Autodesk Fusion 360 part; units mm, degrees
(part 4 of 5)
sketch "草图4 (3)" plane through (0, 0, 4.8) normal (0, 0, 1) x (1, 0, 0) in component "03_可换镜像凹纹压片"
  line L0 (-27.9663, -1.3739) -> (-27.8652, -2.7445)
  line L1 (-27.8652, -2.7445) -> (-27.6969, -4.1085)
  line L2 (-27.6969, -4.1085) -> (-27.462, -5.4625)
  line L3 (-27.462, -5.4625) -> (-27.1609, -6.8034)
  line L4 (-27.1609, -6.8034) -> (-26.7943, -8.128)
  line L5 (-26.7943, -8.128) -> (-26.3632, -9.4329)
  line L6 (-26.3632, -9.4329) -> (-25.8686, -10.7151)
  line L7 (-25.8686, -10.7151) -> (-25.3117, -11.9715)
  line L8 (-25.3117, -11.9715) -> (-24.6938, -13.1991)
  line L9 (-24.6938, -13.1991) -> (-24.0164, -14.3949)
  line L10 (-24.0164, -14.3949) -> (-23.2811, -15.556)
  line L11 (-23.2811, -15.556) -> (-22.4898, -16.6796)
  line L12 (-22.4898, -16.6796) -> (-21.6443, -17.763)
  line L13 (-21.6443, -17.763) -> (-20.7466, -18.8037)
  line L14 (-20.7466, -18.8037) -> (-19.799, -19.799)
  line L15 (-19.799, -19.799) -> (-18.8037, -20.7466)
  line L16 (-18.8037, -20.7466) -> (-17.763, -21.6443)
  line L17 (-17.763, -21.6443) -> (-16.6796, -22.4898)
  line L18 (-16.6796, -22.4898) -> (-15.556, -23.2811)
  line L19 (-15.556, -23.2811) -> (-14.3949, -24.0164)
  line L20 (-14.3949, -24.0164) -> (-13.1991, -24.6938)
  line L21 (-13.1991, -24.6938) -> (-11.9715, -25.3117)
  line L22 (-11.9715, -25.3117) -> (-10.7151, -25.8686)
  line L23 (-10.7151, -25.8686) -> (-9.4329, -26.3632)
  line L24 (-9.4329, -26.3632) -> (-8.128, -26.7943)
  line L25 (-8.128, -26.7943) -> (-6.8034, -27.1609)
  line L26 (-6.8034, -27.1609) -> (-5.4625, -27.462)
  line L27 (-5.4625, -27.462) -> (-4.1085, -27.6969)
  line L28 (-4.1085, -27.6969) -> (-2.7445, -27.8652)
  line L29 (-2.7445, -27.8652) -> (-1.3739, -27.9663)
  line L30 (-1.3739, -27.9663) -> (0, -28)
  line L31 (0, -28) -> (1.3739, -27.9663)
  line L32 (1.3739, -27.9663) -> (2.7445, -27.8652)
  line L33 (2.7445, -27.8652) -> (4.1085, -27.6969)
  line L34 (4.1085, -27.6969) -> (5.4625, -27.462)
  line L35 (5.4625, -27.462) -> (6.8034, -27.1609)
  line L36 (6.8034, -27.1609) -> (8.128, -26.7943)
  line L37 (8.128, -26.7943) -> (9.4329, -26.3632)
  line L38 (9.4329, -26.3632) -> (10.7151, -25.8686)
  line L39 (10.7151, -25.8686) -> (11.9715, -25.3117)
  line L40 (11.9715, -25.3117) -> (13.1991, -24.6938)
  line L41 (13.1991, -24.6938) -> (14.3949, -24.0164)
  line L42 (14.3949, -24.0164) -> (15.556, -23.2811)
  line L43 (15.556, -23.2811) -> (16.6796, -22.4898)
  line L44 (16.6796, -22.4898) -> (17.763, -21.6443)
  line L45 (17.763, -21.6443) -> (18.8037, -20.7466)
  line L46 (18.8037, -20.7466) -> (19.799, -19.799)
  line L47 (19.799, -19.799) -> (20.7466, -18.8037)
  line L48 (20.7466, -18.8037) -> (21.6443, -17.763)
  line L49 (21.6443, -17.763) -> (22.4898, -16.6796)
  line L50 (22.4898, -16.6796) -> (23.2811, -15.556)
  line L51 (23.2811, -15.556) -> (24.0164, -14.3949)
  line L52 (24.0164, -14.3949) -> (24.6938, -13.1991)
  line L53 (24.6938, -13.1991) -> (25.3117, -11.9715)
  line L54 (25.3117, -11.9715) -> (25.8686, -10.7151)
  line L55 (25.8686, -10.7151) -> (26.3632, -9.4329)
  line L56 (26.3632, -9.4329) -> (26.7943, -8.128)
  line L57 (26.7943, -8.128) -> (27.1609, -6.8034)
  line L58 (27.1609, -6.8034) -> (27.462, -5.4625)
  line L59 (27.462, -5.4625) -> (27.6969, -4.1085)
  line L60 (27.6969, -4.1085) -> (27.8652, -2.7445)
  line L61 (27.8652, -2.7445) -> (27.9663, -1.3739)
  line L62 (27.9663, -1.3739) -> (28, 0)
  line L63 (28, 0) -> (27.9663, 1.3739)
  line L64 (27.9663, 1.3739) -> (27.8652, 2.7445)
  line L65 (27.8652, 2.7445) -> (27.6969, 4.1085)
  line L66 (27.6969, 4.1085) -> (27.462, 5.4625)
  line L67 (27.462, 5.4625) -> (27.1609, 6.8034)
  line L68 (27.1609, 6.8034) -> (26.7943, 8.128)
  line L69 (26.7943, 8.128) -> (26.3632, 9.4329)
  line L70 (26.3632, 9.4329) -> (25.8686, 10.7151)
  line L71 (25.8686, 10.7151) -> (25.3117, 11.9715)
  line L72 (25.3117, 11.9715) -> (24.6938, 13.1991)
  line L73 (24.6938, 13.1991) -> (24.0164, 14.3949)
  line L74 (24.0164, 14.3949) -> (23.2811, 15.556)
  line L75 (23.2811, 15.556) -> (22.4898, 16.6796)
  line L76 (22.4898, 16.6796) -> (21.6443, 17.763)
  line L77 (21.6443, 17.763) -> (20.7466, 18.8037)
  line L78 (20.7466, 18.8037) -> (19.799, 19.799)
  line L79 (19.799, 19.799) -> (18.8037, 20.7466)
  line L80 (18.8037, 20.7466) -> (17.763, 21.6443)
  line L81 (17.763, 21.6443) -> (16.6796, 22.4898)
  line L82 (16.6796, 22.4898) -> (15.556, 23.2811)
  line L83 (15.556, 23.2811) -> (14.3949, 24.0164)
  line L84 (14.3949, 24.0164) -> (13.1991, 24.6938)
  line L85 (13.1991, 24.6938) -> (11.9715, 25.3117)
  line L86 (11.9715, 25.3117) -> (10.7151, 25.8686)
  line L87 (10.7151, 25.8686) -> (9.4329, 26.3632)
  line L88 (9.4329, 26.3632) -> (8.128, 26.7943)
  line L89 (8.128, 26.7943) -> (6.8034, 27.1609)
  line L90 (6.8034, 27.1609) -> (5.4625, 27.462)
  line L91 (5.4625, 27.462) -> (4.1085, 27.6969)
  line L92 (4.1085, 27.6969) -> (2.7445, 27.8652)
  line L93 (2.7445, 27.8652) -> (1.3739, 27.9663)
  line L94 (1.3739, 27.9663) -> (0, 28)
  line L95 (0, 28) -> (-1.3739, 27.9663)
  line L96 (-1.3739, 27.9663) -> (-2.7445, 27.8652)
  line L97 (-2.7445, 27.8652) -> (-4.1085, 27.6969)
  line L98 (-4.1085, 27.6969) -> (-5.4625, 27.462)
  line L99 (-5.4625, 27.462) -> (-6.8034, 27.1609)
  line L100 (-6.8034, 27.1609) -> (-8.128, 26.7943)
  line L101 (-8.128, 26.7943) -> (-9.4329, 26.3632)
  line L102 (-9.4329, 26.3632) -> (-10.7151, 25.8686)
  line L103 (-10.7151, 25.8686) -> (-11.9715, 25.3117)
  line L104 (-11.9715, 25.3117) -> (-13.1991, 24.6938)
  line L105 (-13.1991, 24.6938) -> (-14.3949, 24.0164)
  line L106 (-14.3949, 24.0164) -> (-15.556, 23.2811)
  line L107 (-15.556, 23.2811) -> (-16.6796, 22.4898)
  line L108 (-16.6796, 22.4898) -> (-17.763, 21.6443)
  line L109 (-17.763, 21.6443) -> (-18.8037, 20.7466)
  line L110 (-18.8037, 20.7466) -> (-19.799, 19.799)
  line L111 (-19.799, 19.799) -> (-20.7466, 18.8037)
  line L112 (-20.7466, 18.8037) -> (-21.6443, 17.763)
  line L113 (-21.6443, 17.763) -> (-22.4898, 16.6796)
  line L114 (-22.4898, 16.6796) -> (-23.2811, 15.556)
  line L115 (-23.2811, 15.556) -> (-24.0164, 14.3949)
  line L116 (-24.0164, 14.3949) -> (-24.6938, 13.1991)
  line L117 (-24.6938, 13.1991) -> (-25.3117, 11.9715)
  line L118 (-25.3117, 11.9715) -> (-25.8686, 10.7151)
  line L119 (-25.8686, 10.7151) -> (-26.3632, 9.4329)
  line L120 (-26.3632, 9.4329) -> (-26.7943, 8.128)
  line L121 (-26.7943, 8.128) -> (-27.1609, 6.8034)
  line L122 (-27.1609, 6.8034) -> (-27.462, 5.4625)
  line L123 (-27.462, 5.4625) -> (-27.6969, 4.1085)
  line L124 (-27.6969, 4.1085) -> (-27.8652, 2.7445)
  line L125 (-27.8652, 2.7445) -> (-27.9663, 1.3739)
  line L126 (-27.9663, 1.3739) -> (-28, 0)
  line L127 (-28, 0) -> (-27.9663, -1.3739)
  line L128 (-27.1, 0) -> (-27.0674, 1.3297)
  line L129 (-27.0674, 1.3297) -> (-26.9695, 2.6563)
  line L130 (-26.9695, 2.6563) -> (-26.8067, 3.9764)
  line L131 (-26.8067, 3.9764) -> (-26.5793, 5.2869)
  line L132 (-26.5793, 5.2869) -> (-26.2878, 6.5848)
  line L133 (-26.2878, 6.5848) -> (-25.9331, 7.8667)
  line L134 (-25.9331, 7.8667) -> (-25.5158, 9.1297)
  line L135 (-25.5158, 9.1297) -> (-25.0371, 10.3707)
  line L136 (-25.0371, 10.3707) -> (-24.4981, 11.5867)
  line L137 (-24.4981, 11.5867) -> (-23.9001, 12.7749)
  line L138 (-23.9001, 12.7749) -> (-23.2444, 13.9322)
  line L139 (-23.2444, 13.9322) -> (-22.5328, 15.056)
  line L140 (-22.5328, 15.056) -> (-21.7669, 16.1435)
  line L141 (-21.7669, 16.1435) -> (-20.9486, 17.1921)
  line L142 (-20.9486, 17.1921) -> (-20.0798, 18.1992)
  line L143 (-20.0798, 18.1992) -> (-19.1626, 19.1626)
  line L144 (-19.1626, 19.1626) -> (-18.1992, 20.0798)
  line L145 (-18.1992, 20.0798) -> (-17.1921, 20.9486)
  line L146 (-17.1921, 20.9486) -> (-16.1435, 21.7669)
  line L147 (-16.1435, 21.7669) -> (-15.056, 22.5328)
  line L148 (-15.056, 22.5328) -> (-13.9322, 23.2444)
  line L149 (-13.9322, 23.2444) -> (-12.7749, 23.9001)
  line L150 (-12.7749, 23.9001) -> (-11.5867, 24.4981)
  line L151 (-11.5867, 24.4981) -> (-10.3707, 25.0371)
  line L152 (-10.3707, 25.0371) -> (-9.1297, 25.5158)
  line L153 (-9.1297, 25.5158) -> (-7.8667, 25.9331)
  line L154 (-7.8667, 25.9331) -> (-6.5848, 26.2878)
  line L155 (-6.5848, 26.2878) -> (-5.2869, 26.5793)
  line L156 (-5.2869, 26.5793) -> (-3.9764, 26.8067)
  line L157 (-3.9764, 26.8067) -> (-2.6563, 26.9695)
  line L158 (-2.6563, 26.9695) -> (-1.3297, 27.0674)
  line L159 (-1.3297, 27.0674) -> (0, 27.1)
  line L160 (0, 27.1) -> (1.3297, 27.0674)
  line L161 (1.3297, 27.0674) -> (2.6563, 26.9695)
  line L162 (2.6563, 26.9695) -> (3.9764, 26.8067)
  line L163 (3.9764, 26.8067) -> (5.2869, 26.5793)
  line L164 (5.2869, 26.5793) -> (6.5848, 26.2878)
  line L165 (6.5848, 26.2878) -> (7.8667, 25.9331)
  line L166 (7.8667, 25.9331) -> (9.1297, 25.5158)
  line L167 (9.1297, 25.5158) -> (10.3707, 25.0371)
  line L168 (10.3707, 25.0371) -> (11.5867, 24.4981)
  line L169 (11.5867, 24.4981) -> (12.7749, 23.9001)
  line L170 (12.7749, 23.9001) -> (13.9322, 23.2444)
  line L171 (13.9322, 23.2444) -> (15.056, 22.5328)
  line L172 (15.056, 22.5328) -> (16.1435, 21.7669)
  line L173 (16.1435, 21.7669) -> (17.1921, 20.9486)
  line L174 (17.1921, 20.9486) -> (18.1992, 20.0798)
  line L175 (18.1992, 20.0798) -> (19.1626, 19.1626)
  line L176 (19.1626, 19.1626) -> (20.0798, 18.1992)
  line L177 (20.0798, 18.1992) -> (20.9486, 17.1921)
  line L178 (20.9486, 17.1921) -> (21.7669, 16.1435)
  line L179 (21.7669, 16.1435) -> (22.5328, 15.056)
  line L180 (22.5328, 15.056) -> (23.2444, 13.9322)
  line L181 (23.2444, 13.9322) -> (23.9001, 12.7749)
  line L182 (23.9001, 12.7749) -> (24.4981, 11.5867)
  line L183 (24.4981, 11.5867) -> (25.0371, 10.3707)
  line L184 (25.0371, 10.3707) -> (25.5158, 9.1297)
  line L185 (25.5158, 9.1297) -> (25.9331, 7.8667)
  line L186 (25.9331, 7.8667) -> (26.2878, 6.5848)
  line L187 (26.2878, 6.5848) -> (26.5793, 5.2869)
  line L188 (26.5793, 5.2869) -> (26.8067, 3.9764)
  line L189 (26.8067, 3.9764) -> (26.9695, 2.6563)
  line L190 (26.9695, 2.6563) -> (27.0674, 1.3297)
  line L191 (27.0674, 1.3297) -> (27.1, 0)
  line L192 (27.1, 0) -> (27.0674, -1.3297)
  line L193 (27.0674, -1.3297) -> (26.9695, -2.6563)
  line L194 (26.9695, -2.6563) -> (26.8067, -3.9764)
  line L195 (26.8067, -3.9764) -> (26.5793, -5.2869)
  line L196 (26.5793, -5.2869) -> (26.2878, -6.5848)
  line L197 (26.2878, -6.5848) -> (25.9331, -7.8667)
  line L198 (25.9331, -7.8667) -> (25.5158, -9.1297)
  line L199 (25.5158, -9.1297) -> (25.0371, -10.3707)
  line L200 (25.0371, -10.3707) -> (24.4981, -11.5867)
  line L201 (24.4981, -11.5867) -> (23.9001, -12.7749)
  line L202 (23.9001, -12.7749) -> (23.2444, -13.9322)
  line L203 (23.2444, -13.9322) -> (22.5328, -15.056)
  line L204 (22.5328, -15.056) -> (21.7669, -16.1435)
  line L205 (21.7669, -16.1435) -> (20.9486, -17.1921)
  line L206 (20.9486, -17.1921) -> (20.0798, -18.1992)
  line L207 (20.0798, -18.1992) -> (19.1626, -19.1626)
  line L208 (19.1626, -19.1626) -> (18.1992, -20.0798)
  line L209 (18.1992, -20.0798) -> (17.1921, -20.9486)
  line L210 (17.1921, -20.9486) -> (16.1435, -21.7669)
  line L211 (16.1435, -21.7669) -> (15.056, -22.5328)
  line L212 (15.056, -22.5328) -> (13.9322, -23.2444)
  line L213 (13.9322, -23.2444) -> (12.7749, -23.9001)
  line L214 (12.7749, -23.9001) -> (11.5867, -24.4981)
  line L215 (11.5867, -24.4981) -> (10.3707, -25.0371)
  line L216 (10.3707, -25.0371) -> (9.1297, -25.5158)
  line L217 (9.1297, -25.5158) -> (7.8667, -25.9331)
  line L218 (7.8667, -25.9331) -> (6.5848, -26.2878)
  line L219 (6.5848, -26.2878) -> (5.2869, -26.5793)
  line L220 (5.2869, -26.5793) -> (3.9764, -26.8067)
  line L221 (3.9764, -26.8067) -> (2.6563, -26.9695)
  line L222 (2.6563, -26.9695) -> (1.3297, -27.0674)
  line L223 (1.3297, -27.0674) -> (0, -27.1)
  line L224 (0, -27.1) -> (-1.3297, -27.0674)
  line L225 (-1.3297, -27.0674) -> (-2.6563, -26.9695)
  line L226 (-2.6563, -26.9695) -> (-3.9764, -26.8067)
  line L227 (-3.9764, -26.8067) -> (-5.2869, -26.5793)
  line L228 (-5.2869, -26.5793) -> (-6.5848, -26.2878)
  line L229 (-6.5848, -26.2878) -> (-7.8667, -25.9331)
  line L230 (-7.8667, -25.9331) -> (-9.1297, -25.5158)
  line L231 (-9.1297, -25.5158) -> (-10.3707, -25.0371)
  line L232 (-10.3707, -25.0371) -> (-11.5867, -24.4981)
  line L233 (-11.5867, -24.4981) -> (-12.7749, -23.9001)
  line L234 (-12.7749, -23.9001) -> (-13.9322, -23.2444)
  line L235 (-13.9322, -23.2444) -> (-15.056, -22.5328)
  line L236 (-15.056, -22.5328) -> (-16.1435, -21.7669)
  line L237 (-16.1435, -21.7669) -> (-17.1921, -20.9486)
  line L238 (-17.1921, -20.9486) -> (-18.1992, -20.0798)
  line L239 (-18.1992, -20.0798) -> (-19.1626, -19.1626)
  line L240 (-19.1626, -19.1626) -> (-20.0798, -18.1992)
  line L241 (-20.0798, -18.1992) -> (-20.9486, -17.1921)
  line L242 (-20.9486, -17.1921) -> (-21.7669, -16.1435)
  line L243 (-21.7669, -16.1435) -> (-22.5328, -15.056)
  line L244 (-22.5328, -15.056) -> (-23.2444, -13.9322)
  line L245 (-23.2444, -13.9322) -> (-23.9001, -12.7749)
  line L246 (-23.9001, -12.7749) -> (-24.4981, -11.5867)
  line L247 (-24.4981, -11.5867) -> (-25.0371, -10.3707)
  line L248 (-25.0371, -10.3707) -> (-25.5158, -9.1297)
  line L249 (-25.5158, -9.1297) -> (-25.9331, -7.8667)
  line L250 (-25.9331, -7.8667) -> (-26.2878, -6.5848)
  line L251 (-26.2878, -6.5848) -> (-26.5793, -5.2869)
  line L252 (-26.5793, -5.2869) -> (-26.8067, -3.9764)
  line L253 (-26.8067, -3.9764) -> (-26.9695, -2.6563)
  line L254 (-26.9695, -2.6563) -> (-27.0674, -1.3297)
  line L255 (-27.0674, -1.3297) -> (-27.1, 0)
extrude "镜像凹纹_001 (1)" cut sketch "草图4 (3)" along normal blind 1.23 bodies 3 in component "03_可换镜像凹纹压片"
ref_plane "工作平面4" through (0, 0, 4.8) normal (0, 0, 1) x (1, 0, 0) in component "03_可换镜像凹纹压片"
sketch "草图5 (3)" plane through (0, 0, 4.8) normal (0, 0, 1) x (1, 0, 0) in component "03_可换镜像凹纹压片"
  line L0 (-18.4577, -0.9068) -> (-18.391, -1.8114)
  line L1 (-18.391, -1.8114) -> (-18.28, -2.7116)
  line L2 (-18.28, -2.7116) -> (-18.1249, -3.6053)
  line L3 (-18.1249, -3.6053) -> (-17.9262, -4.4903)
  line L4 (-17.9262, -4.4903) -> (-17.6843, -5.3645)
  line L5 (-17.6843, -5.3645) -> (-17.3997, -6.2257)
  line L6 (-17.3997, -6.2257) -> (-17.0733, -7.072)
  line L7 (-17.0733, -7.072) -> (-16.7057, -7.9012)
  line L8 (-16.7057, -7.9012) -> (-16.2979, -8.7114)
  line L9 (-16.2979, -8.7114) -> (-15.8508, -9.5006)
  line L10 (-15.8508, -9.5006) -> (-15.3656, -10.2669)
  line L11 (-15.3656, -10.2669) -> (-14.8433, -11.0085)
  line L12 (-14.8433, -11.0085) -> (-14.2852, -11.7236)
  line L13 (-14.2852, -11.7236) -> (-13.6928, -12.4104)
  line L14 (-13.6928, -12.4104) -> (-13.0673, -13.0673)
  line L15 (-13.0673, -13.0673) -> (-12.4104, -13.6928)
  line L16 (-12.4104, -13.6928) -> (-11.7236, -14.2852)
  line L17 (-11.7236, -14.2852) -> (-11.0085, -14.8433)
  line L18 (-11.0085, -14.8433) -> (-10.2669, -15.3656)
  line L19 (-10.2669, -15.3656) -> (-9.5006, -15.8508)
  line L20 (-9.5006, -15.8508) -> (-8.7114, -16.2979)
  line L21 (-8.7114, -16.2979) -> (-7.9012, -16.7057)
  line L22 (-7.9012, -16.7057) -> (-7.072, -17.0733)
  line L23 (-7.072, -17.0733) -> (-6.2257, -17.3997)
  line L24 (-6.2257, -17.3997) -> (-5.3645, -17.6843)
  line L25 (-5.3645, -17.6843) -> (-4.4903, -17.9262)
  line L26 (-4.4903, -17.9262) -> (-3.6053, -18.1249)
  line L27 (-3.6053, -18.1249) -> (-2.7116, -18.28)
  line L28 (-2.7116, -18.28) -> (-1.8114, -18.391)
  line L29 (-1.8114, -18.391) -> (-0.9068, -18.4577)
  line L30 (-0.9068, -18.4577) -> (0, -18.48)
  line L31 (0, -18.48) -> (0.9068, -18.4577)
  line L32 (0.9068, -18.4577) -> (1.8114, -18.391)
  line L33 (1.8114, -18.391) -> (2.7116, -18.28)
  line L34 (2.7116, -18.28) -> (3.6053, -18.1249)
  line L35 (3.6053, -18.1249) -> (4.4903, -17.9262)
  line L36 (4.4903, -17.9262) -> (5.3645, -17.6843)
  line L37 (5.3645, -17.6843) -> (6.2257, -17.3997)
  line L38 (6.2257, -17.3997) -> (7.072, -17.0733)
  line L39 (7.072, -17.0733) -> (7.9012, -16.7057)
  line L40 (7.9012, -16.7057) -> (8.7114, -16.2979)
  line L41 (8.7114, -16.2979) -> (9.5006, -15.8508)
  line L42 (9.5006, -15.8508) -> (10.2669, -15.3656)
  line L43 (10.2669, -15.3656) -> (11.0085, -14.8433)
  line L44 (11.0085, -14.8433) -> (11.7236, -14.2852)
  line L45 (11.7236, -14.2852) -> (12.4104, -13.6928)
  line L46 (12.4104, -13.6928) -> (13.0673, -13.0673)
  line L47 (13.0673, -13.0673) -> (13.6928, -12.4104)
  line L48 (13.6928, -12.4104) -> (14.2852, -11.7236)
  line L49 (14.2852, -11.7236) -> (14.8433, -11.0085)
  line L50 (14.8433, -11.0085) -> (15.3656, -10.2669)
  line L51 (15.3656, -10.2669) -> (15.8508, -9.5006)
  line L52 (15.8508, -9.5006) -> (16.2979, -8.7114)
  line L53 (16.2979, -8.7114) -> (16.7057, -7.9012)
  line L54 (16.7057, -7.9012) -> (17.0733, -7.072)
  line L55 (17.0733, -7.072) -> (17.3997, -6.2257)
  line L56 (17.3997, -6.2257) -> (17.6843, -5.3645)
  line L57 (17.6843, -5.3645) -> (17.9262, -4.4903)
  line L58 (17.9262, -4.4903) -> (18.1249, -3.6053)
  line L59 (18.1249, -3.6053) -> (18.28, -2.7116)
  line L60 (18.28, -2.7116) -> (18.391, -1.8114)
  line L61 (18.391, -1.8114) -> (18.4577, -0.9068)
  line L62 (18.4577, -0.9068) -> (18.48, 0)
  line L63 (18.48, 0) -> (18.4577, 0.9068)
  line L64 (18.4577, 0.9068) -> (18.391, 1.8114)
  line L65 (18.391, 1.8114) -> (18.28, 2.7116)
  line L66 (18.28, 2.7116) -> (18.1249, 3.6053)
  line L67 (18.1249, 3.6053) -> (17.9262, 4.4903)
  line L68 (17.9262, 4.4903) -> (17.6843, 5.3645)
  line L69 (17.6843, 5.3645) -> (17.3997, 6.2257)
  line L70 (17.3997, 6.2257) -> (17.0733, 7.072)
  line L71 (17.0733, 7.072) -> (16.7057, 7.9012)
  line L72 (16.7057, 7.9012) -> (16.2979, 8.7114)
  line L73 (16.2979, 8.7114) -> (15.8508, 9.5006)
  line L74 (15.8508, 9.5006) -> (15.3656, 10.2669)
  line L75 (15.3656, 10.2669) -> (14.8433, 11.0085)
  line L76 (14.8433, 11.0085) -> (14.2852, 11.7236)
  line L77 (14.2852, 11.7236) -> (13.6928, 12.4104)
  line L78 (13.6928, 12.4104) -> (13.0673, 13.0673)
  line L79 (13.0673, 13.0673) -> (12.4104, 13.6928)
  line L80 (12.4104, 13.6928) -> (11.7236, 14.2852)
  line L81 (11.7236, 14.2852) -> (11.0085, 14.8433)
  line L82 (11.0085, 14.8433) -> (10.2669, 15.3656)
  line L83 (10.2669, 15.3656) -> (9.5006, 15.8508)
  line L84 (9.5006, 15.8508) -> (8.7114, 16.2979)
  line L85 (8.7114, 16.2979) -> (7.9012, 16.7057)
  line L86 (7.9012, 16.7057) -> (7.072, 17.0733)
  line L87 (7.072, 17.0733) -> (6.2257, 17.3997)
  line L88 (6.2257, 17.3997) -> (5.3645, 17.6843)
  line L89 (5.3645, 17.6843) -> (4.4903, 17.9262)
  line L90 (4.4903, 17.9262) -> (3.6053, 18.1249)
  line L91 (3.6053, 18.1249) -> (2.7116, 18.28)
  line L92 (2.7116, 18.28) -> (1.8114, 18.391)
  line L93 (1.8114, 18.391) -> (0.9068, 18.4577)
  line L94 (0.9068, 18.4577) -> (0, 18.48)
  line L95 (0, 18.48) -> (-0.9068, 18.4577)
  line L96 (-0.9068, 18.4577) -> (-1.8114, 18.391)
  line L97 (-1.8114, 18.391) -> (-2.7116, 18.28)
  line L98 (-2.7116, 18.28) -> (-3.6053, 18.1249)
  line L99 (-3.6053, 18.1249) -> (-4.4903, 17.9262)
  line L100 (-4.4903, 17.9262) -> (-5.3645, 17.6843)
  line L101 (-5.3645, 17.6843) -> (-6.2257, 17.3997)
  line L102 (-6.2257, 17.3997) -> (-7.072, 17.0733)
  line L103 (-7.072, 17.0733) -> (-7.9012, 16.7057)
  line L104 (-7.9012, 16.7057) -> (-8.7114, 16.2979)
  line L105 (-8.7114, 16.2979) -> (-9.5006, 15.8508)
  line L106 (-9.5006, 15.8508) -> (-10.2669, 15.3656)
  line L107 (-10.2669, 15.3656) -> (-11.0085, 14.8433)
  line L108 (-11.0085, 14.8433) -> (-11.7236, 14.2852)
  line L109 (-11.7236, 14.2852) -> (-12.4104, 13.6928)
  line L110 (-12.4104, 13.6928) -> (-13.0673, 13.0673)
  line L111 (-13.0673, 13.0673) -> (-13.6928, 12.4104)
  line L112 (-13.6928, 12.4104) -> (-14.2852, 11.7236)
  line L113 (-14.2852, 11.7236) -> (-14.8433, 11.0085)
  line L114 (-14.8433, 11.0085) -> (-15.3656, 10.2669)
  line L115 (-15.3656, 10.2669) -> (-15.8508, 9.5006)
  line L116 (-15.8508, 9.5006) -> (-16.2979, 8.7114)
  line L117 (-16.2979, 8.7114) -> (-16.7057, 7.9012)
  line L118 (-16.7057, 7.9012) -> (-17.0733, 7.072)
  line L119 (-17.0733, 7.072) -> (-17.3997, 6.2257)
  line L120 (-17.3997, 6.2257) -> (-17.6843, 5.3645)
  line L121 (-17.6843, 5.3645) -> (-17.9262, 4.4903)
  line L122 (-17.9262, 4.4903) -> (-18.1249, 3.6053)
  line L123 (-18.1249, 3.6053) -> (-18.28, 2.7116)
  line L124 (-18.28, 2.7116) -> (-18.391, 1.8114)
  line L125 (-18.391, 1.8114) -> (-18.4577, 0.9068)
  line L126 (-18.4577, 0.9068) -> (-18.48, 0)
  line L127 (-18.48, 0) -> (-18.4577, -0.9068)
  line L128 (-17.63, 0) -> (-17.6088, 0.8651)
  line L129 (-17.6088, 0.8651) -> (-17.5451, 1.728)
  line L130 (-17.5451, 1.728) -> (-17.4392, 2.5869)
  line L131 (-17.4392, 2.5869) -> (-17.2912, 3.4394)
  line L132 (-17.2912, 3.4394) -> (-17.1017, 4.2837)
  line L133 (-17.1017, 4.2837) -> (-16.8709, 5.1177)
  line L134 (-16.8709, 5.1177) -> (-16.5994, 5.9394)
  line L135 (-16.5994, 5.9394) -> (-16.288, 6.7467)
  line L136 (-16.288, 6.7467) -> (-15.9373, 7.5378)
  line L137 (-15.9373, 7.5378) -> (-15.5483, 8.3107)
  line L138 (-15.5483, 8.3107) -> (-15.1218, 9.0636)
  line L139 (-15.1218, 9.0636) -> (-14.6588, 9.7947)
  line L140 (-14.6588, 9.7947) -> (-14.1605, 10.5022)
  line L141 (-14.1605, 10.5022) -> (-13.6282, 11.1844)
  line L142 (-13.6282, 11.1844) -> (-13.063, 11.8396)
  line L143 (-13.063, 11.8396) -> (-12.4663, 12.4663)
  line L144 (-12.4663, 12.4663) -> (-11.8396, 13.063)
  line L145 (-11.8396, 13.063) -> (-11.1844, 13.6282)
  line L146 (-11.1844, 13.6282) -> (-10.5022, 14.1605)
  line L147 (-10.5022, 14.1605) -> (-9.7947, 14.6588)
  line L148 (-9.7947, 14.6588) -> (-9.0636, 15.1218)
  line L149 (-9.0636, 15.1218) -> (-8.3107, 15.5483)
  line L150 (-8.3107, 15.5483) -> (-7.5378, 15.9373)
  line L151 (-7.5378, 15.9373) -> (-6.7467, 16.288)
  line L152 (-6.7467, 16.288) -> (-5.9394, 16.5994)
  line L153 (-5.9394, 16.5994) -> (-5.1177, 16.8709)
  line L154 (-5.1177, 16.8709) -> (-4.2837, 17.1017)
  line L155 (-4.2837, 17.1017) -> (-3.4394, 17.2912)
  line L156 (-3.4394, 17.2912) -> (-2.5869, 17.4392)
  line L157 (-2.5869, 17.4392) -> (-1.728, 17.5451)
  line L158 (-1.728, 17.5451) -> (-0.8651, 17.6088)
  line L159 (-0.8651, 17.6088) -> (0, 17.63)
  line L160 (0, 17.63) -> (0.8651, 17.6088)
  line L161 (0.8651, 17.6088) -> (1.728, 17.5451)
  line L162 (1.728, 17.5451) -> (2.5869, 17.4392)
  line L163 (2.5869, 17.4392) -> (3.4394, 17.2912)
  line L164 (3.4394, 17.2912) -> (4.2837, 17.1017)
  line L165 (4.2837, 17.1017) -> (5.1177, 16.8709)
  line L166 (5.1177, 16.8709) -> (5.9394, 16.5994)
  line L167 (5.9394, 16.5994) -> (6.7467, 16.288)
  line L168 (6.7467, 16.288) -> (7.5378, 15.9373)
  line L169 (7.5378, 15.9373) -> (8.3107, 15.5483)
  line L170 (8.3107, 15.5483) -> (9.0636, 15.1218)
  line L171 (9.0636, 15.1218) -> (9.7947, 14.6588)
  line L172 (9.7947, 14.6588) -> (10.5022, 14.1605)
  line L173 (10.5022, 14.1605) -> (11.1844, 13.6282)
  line L174 (11.1844, 13.6282) -> (11.8396, 13.063)
  line L175 (11.8396, 13.063) -> (12.4663, 12.4663)
  line L176 (12.4663, 12.4663) -> (13.063, 11.8396)
  line L177 (13.063, 11.8396) -> (13.6282, 11.1844)
  line L178 (13.6282, 11.1844) -> (14.1605, 10.5022)
  line L179 (14.1605, 10.5022) -> (14.6588, 9.7947)
  line L180 (14.6588, 9.7947) -> (15.1218, 9.0636)
  line L181 (15.1218, 9.0636) -> (15.5483, 8.3107)
  line L182 (15.5483, 8.3107) -> (15.9373, 7.5378)
  line L183 (15.9373, 7.5378) -> (16.288, 6.7467)
  line L184 (16.288, 6.7467) -> (16.5994, 5.9394)
  line L185 (16.5994, 5.9394) -> (16.8709, 5.1177)
  line L186 (16.8709, 5.1177) -> (17.1017, 4.2837)
  line L187 (17.1017, 4.2837) -> (17.2912, 3.4394)
  line L188 (17.2912, 3.4394) -> (17.4392, 2.5869)
  line L189 (17.4392, 2.5869) -> (17.5451, 1.728)
  line L190 (17.5451, 1.728) -> (17.6088, 0.8651)
  line L191 (17.6088, 0.8651) -> (17.63, 0)
  line L192 (17.63, 0) -> (17.6088, -0.8651)
  line L193 (17.6088, -0.8651) -> (17.5451, -1.728)
  line L194 (17.5451, -1.728) -> (17.4392, -2.5869)
  line L195 (17.4392, -2.5869) -> (17.2912, -3.4394)
  line L196 (17.2912, -3.4394) -> (17.1017, -4.2837)
  line L197 (17.1017, -4.2837) -> (16.8709, -5.1177)
  line L198 (16.8709, -5.1177) -> (16.5994, -5.9394)
  line L199 (16.5994, -5.9394) -> (16.288, -6.7467)
  line L200 (16.288, -6.7467) -> (15.9373, -7.5378)
  line L201 (15.9373, -7.5378) -> (15.5483, -8.3107)
  line L202 (15.5483, -8.3107) -> (15.1218, -9.0636)
  line L203 (15.1218, -9.0636) -> (14.6588, -9.7947)
  line L204 (14.6588, -9.7947) -> (14.1605, -10.5022)
  line L205 (14.1605, -10.5022) -> (13.6282, -11.1844)
  line L206 (13.6282, -11.1844) -> (13.063, -11.8396)
  line L207 (13.063, -11.8396) -> (12.4663, -12.4663)
  line L208 (12.4663, -12.4663) -> (11.8396, -13.063)
  line L209 (11.8396, -13.063) -> (11.1844, -13.6282)
  line L210 (11.1844, -13.6282) -> (10.5022, -14.1605)
  line L211 (10.5022, -14.1605) -> (9.7947, -14.6588)
  line L212 (9.7947, -14.6588) -> (9.0636, -15.1218)
  line L213 (9.0636, -15.1218) -> (8.3107, -15.5483)
  line L214 (8.3107, -15.5483) -> (7.5378, -15.9373)
  line L215 (7.5378, -15.9373) -> (6.7467, -16.288)
  line L216 (6.7467, -16.288) -> (5.9394, -16.5994)
  line L217 (5.9394, -16.5994) -> (5.1177, -16.8709)
  line L218 (5.1177, -16.8709) -> (4.2837, -17.1017)
  line L219 (4.2837, -17.1017) -> (3.4394, -17.2912)
  line L220 (3.4394, -17.2912) -> (2.5869, -17.4392)
  line L221 (2.5869, -17.4392) -> (1.728, -17.5451)
  line L222 (1.728, -17.5451) -> (0.8651, -17.6088)
  line L223 (0.8651, -17.6088) -> (0, -17.63)
  line L224 (0, -17.63) -> (-0.8651, -17.6088)
  line L225 (-0.8651, -17.6088) -> (-1.728, -17.5451)
  line L226 (-1.728, -17.5451) -> (-2.5869, -17.4392)
  line L227 (-2.5869, -17.4392) -> (-3.4394, -17.2912)
  line L228 (-3.4394, -17.2912) -> (-4.2837, -17.1017)
  line L229 (-4.2837, -17.1017) -> (-5.1177, -16.8709)
  line L230 (-5.1177, -16.8709) -> (-5.9394, -16.5994)
  line L231 (-5.9394, -16.5994) -> (-6.7467, -16.288)
  line L232 (-6.7467, -16.288) -> (-7.5378, -15.9373)
  line L233 (-7.5378, -15.9373) -> (-8.3107, -15.5483)
  line L234 (-8.3107, -15.5483) -> (-9.0636, -15.1218)
  line L235 (-9.0636, -15.1218) -> (-9.7947, -14.6588)
  line L236 (-9.7947, -14.6588) -> (-10.5022, -14.1605)
  line L237 (-10.5022, -14.1605) -> (-11.1844, -13.6282)
  line L238 (-11.1844, -13.6282) -> (-11.8396, -13.063)
  line L239 (-11.8396, -13.063) -> (-12.4663, -12.4663)
  line L240 (-12.4663, -12.4663) -> (-13.063, -11.8396)
  line L241 (-13.063, -11.8396) -> (-13.6282, -11.1844)
  line L242 (-13.6282, -11.1844) -> (-14.1605, -10.5022)
  line L243 (-14.1605, -10.5022) -> (-14.6588, -9.7947)
  line L244 (-14.6588, -9.7947) -> (-15.1218, -9.0636)
  line L245 (-15.1218, -9.0636) -> (-15.5483, -8.3107)
  line L246 (-15.5483, -8.3107) -> (-15.9373, -7.5378)
  line L247 (-15.9373, -7.5378) -> (-16.288, -6.7467)
  line L248 (-16.288, -6.7467) -> (-16.5994, -5.9394)
  line L249 (-16.5994, -5.9394) -> (-16.8709, -5.1177)
  line L250 (-16.8709, -5.1177) -> (-17.1017, -4.2837)
  line L251 (-17.1017, -4.2837) -> (-17.2912, -3.4394)
  line L252 (-17.2912, -3.4394) -> (-17.4392, -2.5869)
  line L253 (-17.4392, -2.5869) -> (-17.5451, -1.728)
  line L254 (-17.5451, -1.728) -> (-17.6088, -0.8651)
  line L255 (-17.6088, -0.8651) -> (-17.63, 0)
extrude "镜像凹纹_002 (1)" cut sketch "草图5 (3)" along normal blind 1.23 bodies 3 in component "03_可换镜像凹纹压片"
ref_plane "工作平面5" through (0, 0, 4.4) normal (0, 0, 1) x (1, 0, 0) in component "03_可换镜像凹纹压片"
sketch "草图6 (2)" plane through (0, 0, 4.4) normal (0, 0, 1) x (1, 0, 0) in component "03_可换镜像凹纹压片"
  line L0 (-12.5848, -0.6183) -> (-12.5393, -1.235)
  line L1 (-12.5393, -1.235) -> (-12.4636, -1.8488)
  line L2 (-12.4636, -1.8488) -> (-12.3579, -2.4581)
  line L3 (-12.3579, -2.4581) -> (-12.2224, -3.0616)
  line L4 (-12.2224, -3.0616) -> (-12.0574, -3.6576)
  line L5 (-12.0574, -3.6576) -> (-11.8635, -4.2448)
  line L6 (-11.8635, -4.2448) -> (-11.6409, -4.8218)
  line L7 (-11.6409, -4.8218) -> (-11.3903, -5.3872)
  line L8 (-11.3903, -5.3872) -> (-11.1122, -5.9396)
  line L9 (-11.1122, -5.9396) -> (-10.8074, -6.4777)
  line L10 (-10.8074, -6.4777) -> (-10.4765, -7.0002)
  line L11 (-10.4765, -7.0002) -> (-10.1204, -7.5058)
  line L12 (-10.1204, -7.5058) -> (-9.7399, -7.9934)
  line L13 (-9.7399, -7.9934) -> (-9.336, -8.4616)
  line L14 (-9.336, -8.4616) -> (-8.9095, -8.9095)
  line L15 (-8.9095, -8.9095) -> (-8.4616, -9.336)
  line L16 (-8.4616, -9.336) -> (-7.9934, -9.7399)
  line L17 (-7.9934, -9.7399) -> (-7.5058, -10.1204)
  line L18 (-7.5058, -10.1204) -> (-7.0002, -10.4765)
  line L19 (-7.0002, -10.4765) -> (-6.4777, -10.8074)
  line L20 (-6.4777, -10.8074) -> (-5.9396, -11.1122)
  line L21 (-5.9396, -11.1122) -> (-5.3872, -11.3903)
  line L22 (-5.3872, -11.3903) -> (-4.8218, -11.6409)
  line L23 (-4.8218, -11.6409) -> (-4.2448, -11.8635)
  line L24 (-4.2448, -11.8635) -> (-3.6576, -12.0574)
  line L25 (-3.6576, -12.0574) -> (-3.0616, -12.2224)
  line L26 (-3.0616, -12.2224) -> (-2.4581, -12.3579)
  line L27 (-2.4581, -12.3579) -> (-1.8488, -12.4636)
  line L28 (-1.8488, -12.4636) -> (-1.235, -12.5393)
  line L29 (-1.235, -12.5393) -> (-0.6183, -12.5848)
  line L30 (-0.6183, -12.5848) -> (0, -12.6)
  line L31 (0, -12.6) -> (0.6183, -12.5848)
  line L32 (0.6183, -12.5848) -> (1.235, -12.5393)
  line L33 (1.235, -12.5393) -> (1.8488, -12.4636)
  line L34 (1.8488, -12.4636) -> (2.4581, -12.3579)
  line L35 (2.4581, -12.3579) -> (3.0616, -12.2224)
  line L36 (3.0616, -12.2224) -> (3.6576, -12.0574)
  line L37 (3.6576, -12.0574) -> (4.2448, -11.8635)
  line L38 (4.2448, -11.8635) -> (4.8218, -11.6409)
  line L39 (4.8218, -11.6409) -> (5.3872, -11.3903)
  line L40 (5.3872, -11.3903) -> (5.9396, -11.1122)
  line L41 (5.9396, -11.1122) -> (6.4777, -10.8074)
  line L42 (6.4777, -10.8074) -> (7.0002, -10.4765)
  line L43 (7.0002, -10.4765) -> (7.5058, -10.1204)
  line L44 (7.5058, -10.1204) -> (7.9934, -9.7399)
  line L45 (7.9934, -9.7399) -> (8.4616, -9.336)
  line L46 (8.4616, -9.336) -> (8.9095, -8.9095)
  line L47 (8.9095, -8.9095) -> (9.336, -8.4616)
  line L48 (9.336, -8.4616) -> (9.7399, -7.9934)
  line L49 (9.7399, -7.9934) -> (10.1204, -7.5058)
  line L50 (10.1204, -7.5058) -> (10.4765, -7.0002)
  line L51 (10.4765, -7.0002) -> (10.8074, -6.4777)
  line L52 (10.8074, -6.4777) -> (11.1122, -5.9396)
  line L53 (11.1122, -5.9396) -> (11.3903, -5.3872)
  line L54 (11.3903, -5.3872) -> (11.6409, -4.8218)
  line L55 (11.6409, -4.8218) -> (11.8635, -4.2448)
  line L56 (11.8635, -4.2448) -> (12.0574, -3.6576)
  line L57 (12.0574, -3.6576) -> (12.2224, -3.0616)
  line L58 (12.2224, -3.0616) -> (12.3579, -2.4581)
  line L59 (12.3579, -2.4581) -> (12.4636, -1.8488)
  line L60 (12.4636, -1.8488) -> (12.5393, -1.235)
  line L61 (12.5393, -1.235) -> (12.5848, -0.6183)
  line L62 (12.5848, -0.6183) -> (12.6, 0)
  line L63 (12.6, 0) -> (12.5848, 0.6183)
  line L64 (12.5848, 0.6183) -> (12.5393, 1.235)
  line L65 (12.5393, 1.235) -> (12.4636, 1.8488)
  line L66 (12.4636, 1.8488) -> (12.3579, 2.4581)
  line L67 (12.3579, 2.4581) -> (12.2224, 3.0616)
  line L68 (12.2224, 3.0616) -> (12.0574, 3.6576)
  line L69 (12.0574, 3.6576) -> (11.8635, 4.2448)
  line L70 (11.8635, 4.2448) -> (11.6409, 4.8218)
  line L71 (11.6409, 4.8218) -> (11.3903, 5.3872)
  line L72 (11.3903, 5.3872) -> (11.1122, 5.9396)
  line L73 (11.1122, 5.9396) -> (10.8074, 6.4777)
  line L74 (10.8074, 6.4777) -> (10.4765, 7.0002)
  line L75 (10.4765, 7.0002) -> (10.1204, 7.5058)
  line L76 (10.1204, 7.5058) -> (9.7399, 7.9934)
  line L77 (9.7399, 7.9934) -> (9.336, 8.4616)
  line L78 (9.336, 8.4616) -> (8.9095, 8.9095)
  line L79 (8.9095, 8.9095) -> (8.4616, 9.336)
  line L80 (8.4616, 9.336) -> (7.9934, 9.7399)
  line L81 (7.9934, 9.7399) -> (7.5058, 10.1204)
  line L82 (7.5058, 10.1204) -> (7.0002, 10.4765)
  line L83 (7.0002, 10.4765) -> (6.4777, 10.8074)
  line L84 (6.4777, 10.8074) -> (5.9396, 11.1122)
  line L85 (5.9396, 11.1122) -> (5.3872, 11.3903)
  line L86 (5.3872, 11.3903) -> (4.8218, 11.6409)
  line L87 (4.8218, 11.6409) -> (4.2448, 11.8635)
  line L88 (4.2448, 11.8635) -> (3.6576, 12.0574)
  line L89 (3.6576, 12.0574) -> (3.0616, 12.2224)
  line L90 (3.0616, 12.2224) -> (2.4581, 12.3579)
  line L91 (2.4581, 12.3579) -> (1.8488, 12.4636)
  line L92 (1.8488, 12.4636) -> (1.235, 12.5393)
  line L93 (1.235, 12.5393) -> (0.6183, 12.5848)
  line L94 (0.6183, 12.5848) -> (0, 12.6)
  line L95 (0, 12.6) -> (-0.6183, 12.5848)
  line L96 (-0.6183, 12.5848) -> (-1.235, 12.5393)
  line L97 (-1.235, 12.5393) -> (-1.8488, 12.4636)
  line L98 (-1.8488, 12.4636) -> (-2.4581, 12.3579)
  line L99 (-2.4581, 12.3579) -> (-3.0616, 12.2224)
  line L100 (-3.0616, 12.2224) -> (-3.6576, 12.0574)
  line L101 (-3.6576, 12.0574) -> (-4.2448, 11.8635)
  line L102 (-4.2448, 11.8635) -> (-4.8218, 11.6409)
  line L103 (-4.8218, 11.6409) -> (-5.3872, 11.3903)
  line L104 (-5.3872, 11.3903) -> (-5.9396, 11.1122)
  line L105 (-5.9396, 11.1122) -> (-6.4777, 10.8074)
  line L106 (-6.4777, 10.8074) -> (-7.0002, 10.4765)
  line L107 (-7.0002, 10.4765) -> (-7.5058, 10.1204)
  line L108 (-7.5058, 10.1204) -> (-7.9934, 9.7399)
  line L109 (-7.9934, 9.7399) -> (-8.4616, 9.336)
  line L110 (-8.4616, 9.336) -> (-8.9095, 8.9095)
  line L111 (-8.9095, 8.9095) -> (-9.336, 8.4616)
  line L112 (-9.336, 8.4616) -> (-9.7399, 7.9934)
  line L113 (-9.7399, 7.9934) -> (-10.1204, 7.5058)
  line L114 (-10.1204, 7.5058) -> (-10.4765, 7.0002)
  line L115 (-10.4765, 7.0002) -> (-10.8074, 6.4777)
  line L116 (-10.8074, 6.4777) -> (-11.1122, 5.9396)
  line L117 (-11.1122, 5.9396) -> (-11.3903, 5.3872)
  line L118 (-11.3903, 5.3872) -> (-11.6409, 4.8218)
  line L119 (-11.6409, 4.8218) -> (-11.8635, 4.2448)
  line L120 (-11.8635, 4.2448) -> (-12.0574, 3.6576)
  line L121 (-12.0574, 3.6576) -> (-12.2224, 3.0616)
  line L122 (-12.2224, 3.0616) -> (-12.3579, 2.4581)
  line L123 (-12.3579, 2.4581) -> (-12.4636, 1.8488)
  line L124 (-12.4636, 1.8488) -> (-12.5393, 1.235)
  line L125 (-12.5393, 1.235) -> (-12.5848, 0.6183)
  line L126 (-12.5848, 0.6183) -> (-12.6, 0)
  line L127 (-12.6, 0) -> (-12.5848, -0.6183)
  line L128 (-11.8, 0) -> (-11.7858, 0.579)
  line L129 (-11.7858, 0.579) -> (-11.7432, 1.1566)
  line L130 (-11.7432, 1.1566) -> (-11.6723, 1.7314)
  line L131 (-11.6723, 1.7314) -> (-11.5733, 2.3021)
  line L132 (-11.5733, 2.3021) -> (-11.4464, 2.8672)
  line L133 (-11.4464, 2.8672) -> (-11.2919, 3.4254)
  line L134 (-11.2919, 3.4254) -> (-11.1102, 3.9753)
  line L135 (-11.1102, 3.9753) -> (-10.9018, 4.5157)
  line L136 (-10.9018, 4.5157) -> (-10.6671, 5.0452)
  line L137 (-10.6671, 5.0452) -> (-10.4067, 5.5625)
  line L138 (-10.4067, 5.5625) -> (-10.1212, 6.0664)
  line L139 (-10.1212, 6.0664) -> (-9.8113, 6.5557)
  line L140 (-9.8113, 6.5557) -> (-9.4778, 7.0293)
  line L141 (-9.4778, 7.0293) -> (-9.1215, 7.4858)
  line L142 (-9.1215, 7.4858) -> (-8.7432, 7.9244)
  line L143 (-8.7432, 7.9244) -> (-8.3439, 8.3439)
  line L144 (-8.3439, 8.3439) -> (-7.9244, 8.7432)
  line L145 (-7.9244, 8.7432) -> (-7.4858, 9.1215)
  line L146 (-7.4858, 9.1215) -> (-7.0293, 9.4778)
  line L147 (-7.0293, 9.4778) -> (-6.5557, 9.8113)
  line L148 (-6.5557, 9.8113) -> (-6.0664, 10.1212)
  line L149 (-6.0664, 10.1212) -> (-5.5625, 10.4067)
  line L150 (-5.5625, 10.4067) -> (-5.0452, 10.6671)
  line L151 (-5.0452, 10.6671) -> (-4.5157, 10.9018)
  line L152 (-4.5157, 10.9018) -> (-3.9753, 11.1102)
  line L153 (-3.9753, 11.1102) -> (-3.4254, 11.2919)
  line L154 (-3.4254, 11.2919) -> (-2.8672, 11.4464)
  line L155 (-2.8672, 11.4464) -> (-2.3021, 11.5733)
  line L156 (-2.3021, 11.5733) -> (-1.7314, 11.6723)
  line L157 (-1.7314, 11.6723) -> (-1.1566, 11.7432)
  line L158 (-1.1566, 11.7432) -> (-0.579, 11.7858)
  line L159 (-0.579, 11.7858) -> (0, 11.8)
  line L160 (0, 11.8) -> (0.579, 11.7858)
  line L161 (0.579, 11.7858) -> (1.1566, 11.7432)
  line L162 (1.1566, 11.7432) -> (1.7314, 11.6723)
  line L163 (1.7314, 11.6723) -> (2.3021, 11.5733)
  line L164 (2.3021, 11.5733) -> (2.8672, 11.4464)
  line L165 (2.8672, 11.4464) -> (3.4254, 11.2919)
  line L166 (3.4254, 11.2919) -> (3.9753, 11.1102)
  line L167 (3.9753, 11.1102) -> (4.5157, 10.9018)
  line L168 (4.5157, 10.9018) -> (5.0452, 10.6671)
  line L169 (5.0452, 10.6671) -> (5.5625, 10.4067)
  line L170 (5.5625, 10.4067) -> (6.0664, 10.1212)
  line L171 (6.0664, 10.1212) -> (6.5557, 9.8113)
  line L172 (6.5557, 9.8113) -> (7.0293, 9.4778)
  line L173 (7.0293, 9.4778) -> (7.4858, 9.1215)
  line L174 (7.4858, 9.1215) -> (7.9244, 8.7432)
  line L175 (7.9244, 8.7432) -> (8.3439, 8.3439)
  line L176 (8.3439, 8.3439) -> (8.7432, 7.9244)
  line L177 (8.7432, 7.9244) -> (9.1215, 7.4858)
  line L178 (9.1215, 7.4858) -> (9.4778, 7.0293)
  line L179 (9.4778, 7.0293) -> (9.8113, 6.5557)
  line L180 (9.8113, 6.5557) -> (10.1212, 6.0664)
  line L181 (10.1212, 6.0664) -> (10.4067, 5.5625)
  line L182 (10.4067, 5.5625) -> (10.6671, 5.0452)
  line L183 (10.6671, 5.0452) -> (10.9018, 4.5157)
  line L184 (10.9018, 4.5157) -> (11.1102, 3.9753)
  line L185 (11.1102, 3.9753) -> (11.2919, 3.4254)
  line L186 (11.2919, 3.4254) -> (11.4464, 2.8672)
  line L187 (11.4464, 2.8672) -> (11.5733, 2.3021)
  line L188 (11.5733, 2.3021) -> (11.6723, 1.7314)
  line L189 (11.6723, 1.7314) -> (11.7432, 1.1566)
  line L190 (11.7432, 1.1566) -> (11.7858, 0.579)
  line L191 (11.7858, 0.579) -> (11.8, 0)
  line L192 (11.8, 0) -> (11.7858, -0.579)
  line L193 (11.7858, -0.579) -> (11.7432, -1.1566)
  line L194 (11.7432, -1.1566) -> (11.6723, -1.7314)
  line L195 (11.6723, -1.7314) -> (11.5733, -2.3021)
  line L196 (11.5733, -2.3021) -> (11.4464, -2.8672)
  line L197 (11.4464, -2.8672) -> (11.2919, -3.4254)
  line L198 (11.2919, -3.4254) -> (11.1102, -3.9753)
  line L199 (11.1102, -3.9753) -> (10.9018, -4.5157)
  line L200 (10.9018, -4.5157) -> (10.6671, -5.0452)
  line L201 (10.6671, -5.0452) -> (10.4067, -5.5625)
  line L202 (10.4067, -5.5625) -> (10.1212, -6.0664)
  line L203 (10.1212, -6.0664) -> (9.8113, -6.5557)
  line L204 (9.8113, -6.5557) -> (9.4778, -7.0293)
  line L205 (9.4778, -7.0293) -> (9.1215, -7.4858)
  line L206 (9.1215, -7.4858) -> (8.7432, -7.9244)
  line L207 (8.7432, -7.9244) -> (8.3439, -8.3439)
  line L208 (8.3439, -8.3439) -> (7.9244, -8.7432)
  line L209 (7.9244, -8.7432) -> (7.4858, -9.1215)
  line L210 (7.4858, -9.1215) -> (7.0293, -9.4778)
  line L211 (7.0293, -9.4778) -> (6.5557, -9.8113)
  line L212 (6.5557, -9.8113) -> (6.0664, -10.1212)
  line L213 (6.0664, -10.1212) -> (5.5625, -10.4067)
  line L214 (5.5625, -10.4067) -> (5.0452, -10.6671)
  line L215 (5.0452, -10.6671) -> (4.5157, -10.9018)
  line L216 (4.5157, -10.9018) -> (3.9753, -11.1102)
  line L217 (3.9753, -11.1102) -> (3.4254, -11.2919)
  line L218 (3.4254, -11.2919) -> (2.8672, -11.4464)
  line L219 (2.8672, -11.4464) -> (2.3021, -11.5733)
  line L220 (2.3021, -11.5733) -> (1.7314, -11.6723)
  line L221 (1.7314, -11.6723) -> (1.1566, -11.7432)
  line L222 (1.1566, -11.7432) -> (0.579, -11.7858)
  line L223 (0.579, -11.7858) -> (0, -11.8)
  line L224 (0, -11.8) -> (-0.579, -11.7858)
  line L225 (-0.579, -11.7858) -> (-1.1566, -11.7432)
  line L226 (-1.1566, -11.7432) -> (-1.7314, -11.6723)
  line L227 (-1.7314, -11.6723) -> (-2.3021, -11.5733)
  line L228 (-2.3021, -11.5733) -> (-2.8672, -11.4464)
  line L229 (-2.8672, -11.4464) -> (-3.4254, -11.2919)
  line L230 (-3.4254, -11.2919) -> (-3.9753, -11.1102)
  line L231 (-3.9753, -11.1102) -> (-4.5157, -10.9018)
  line L232 (-4.5157, -10.9018) -> (-5.0452, -10.6671)
  line L233 (-5.0452, -10.6671) -> (-5.5625, -10.4067)
  line L234 (-5.5625, -10.4067) -> (-6.0664, -10.1212)
  line L235 (-6.0664, -10.1212) -> (-6.5557, -9.8113)
  line L236 (-6.5557, -9.8113) -> (-7.0293, -9.4778)
  line L237 (-7.0293, -9.4778) -> (-7.4858, -9.1215)
  line L238 (-7.4858, -9.1215) -> (-7.9244, -8.7432)
  line L239 (-7.9244, -8.7432) -> (-8.3439, -8.3439)
  line L240 (-8.3439, -8.3439) -> (-8.7432, -7.9244)
  line L241 (-8.7432, -7.9244) -> (-9.1215, -7.4858)
  line L242 (-9.1215, -7.4858) -> (-9.4778, -7.0293)
  line L243 (-9.4778, -7.0293) -> (-9.8113, -6.5557)
  line L244 (-9.8113, -6.5557) -> (-10.1212, -6.0664)
  line L245 (-10.1212, -6.0664) -> (-10.4067, -5.5625)
  line L246 (-10.4067, -5.5625) -> (-10.6671, -5.0452)
  line L247 (-10.6671, -5.0452) -> (-10.9018, -4.5157)
  line L248 (-10.9018, -4.5157) -> (-11.1102, -3.9753)
  line L249 (-11.1102, -3.9753) -> (-11.2919, -3.4254)
  line L250 (-11.2919, -3.4254) -> (-11.4464, -2.8672)
  line L251 (-11.4464, -2.8672) -> (-11.5733, -2.3021)
  line L252 (-11.5733, -2.3021) -> (-11.6723, -1.7314)
  line L253 (-11.6723, -1.7314) -> (-11.7432, -1.1566)
  line L254 (-11.7432, -1.1566) -> (-11.7858, -0.579)
  line L255 (-11.7858, -0.579) -> (-11.8, 0)
extrude "镜像凹纹_003 (1)" cut sketch "草图6 (2)" along normal blind 1.63 bodies 3 in component "03_可换镜像凹纹压片"
ref_plane "工作平面6" through (0, 0, 4.4) normal (0, 0, 1) x (1, 0, 0) in component "03_可换镜像凹纹压片"